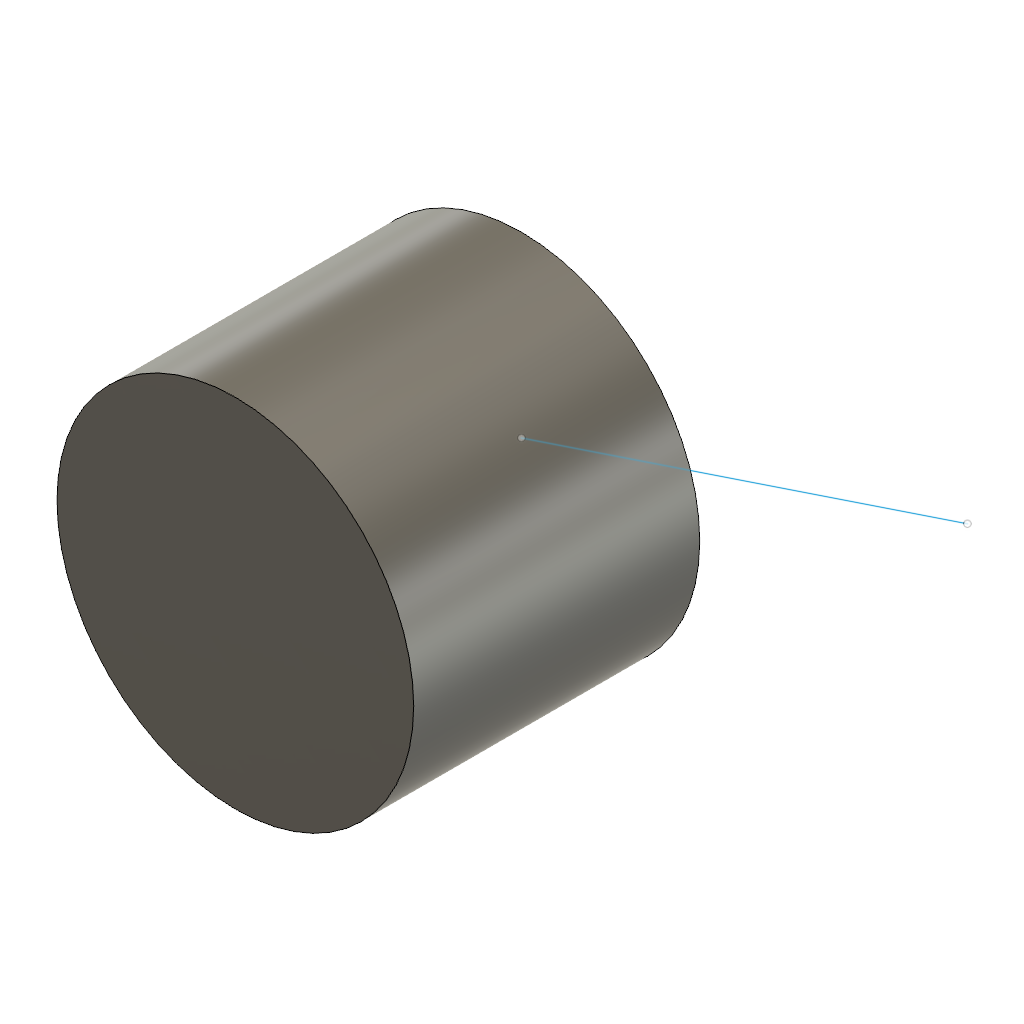
expression_depth (Autodesk Fusion 360 design; units mm, degrees)
part number: 2026-10-20-16-46-59-236
Autodesk Fusion 360 part; units mm, degrees
sketch "UnrelatedSketch" plane through (0, 0, 0) normal (0, 1, 0) x (1, 0, 0)
  line L0 (0, 0) -> (20, 10)
sketch "IndependentProfile0" plane through (0, 0, 0) normal (0, 0, 1) x (1, 0, 0)
  circle A0 centre (0, 0) radius 12
extrude "BlindProbe_0" add sketch "IndependentProfile0" along normal blind 19.25
equation "probeDepth = 9.125 mm"
equation "d2 = probeDepth * 2 + 1 mm"
